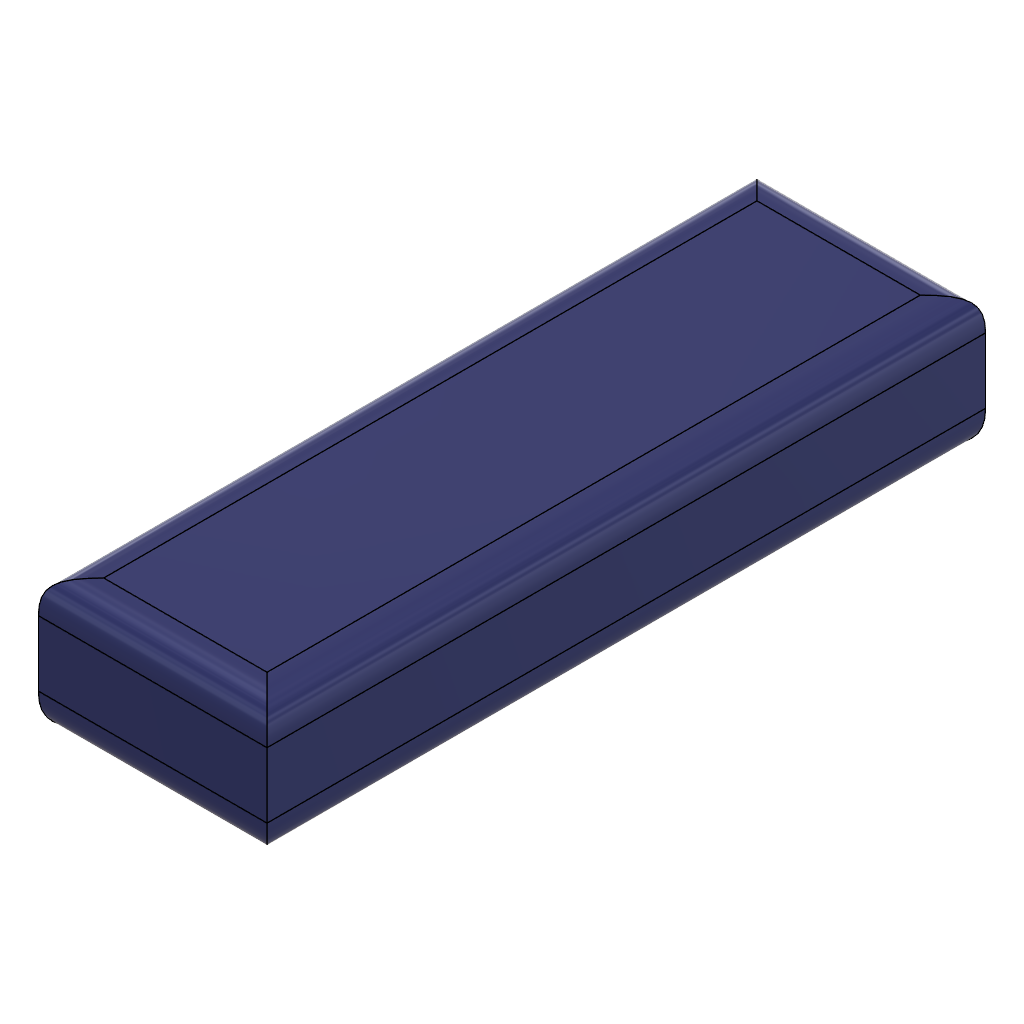
BALANCIN_V1 (Autodesk Fusion 360 archive; units mm, degrees)
design "BATERIA"
part number: 2026-09-12-01-15-48-725
Autodesk Fusion 360 part; units mm, degrees
sketch "Boceto1" plane through (0, 0, 0) normal (0, 1, 0) x (1, 0, 0)
  line L0 (163.423, 76.0371) -> (198.423, 76.0371)
  line L1 (198.423, 76.0371) -> (198.423, -33.9629)
  line L2 (198.423, -33.9629) -> (163.423, -33.9629)
  line L3 (163.423, -33.9629) -> (163.423, 76.0371)
  dimension "d1" = 35
  dimension "d2" = 110
  constraint horizontal L0
  constraint vertical L1
  constraint horizontal L2
  constraint vertical L3
  measures "d1" distance of L0.start L0.end
  measures "d2" distance of L0.start L2.end
extrude "Extruir1" add sketch "Boceto1" along normal blind 20
fillet "Empalme1" radius 5 tangency weight 2 4 edges at (198.423, 20, -21.0371) (180.923, 20, 33.9629) (163.423, 20, -21.0371) (180.923, 20, -76.0371)
fillet "Empalme2" radius 5 tangency weight 2 4 edges at (163.423, 0, -21.0371) (198.423, 0, -21.0371) (180.923, 0, 33.9629) (180.923, 0, -76.0371)

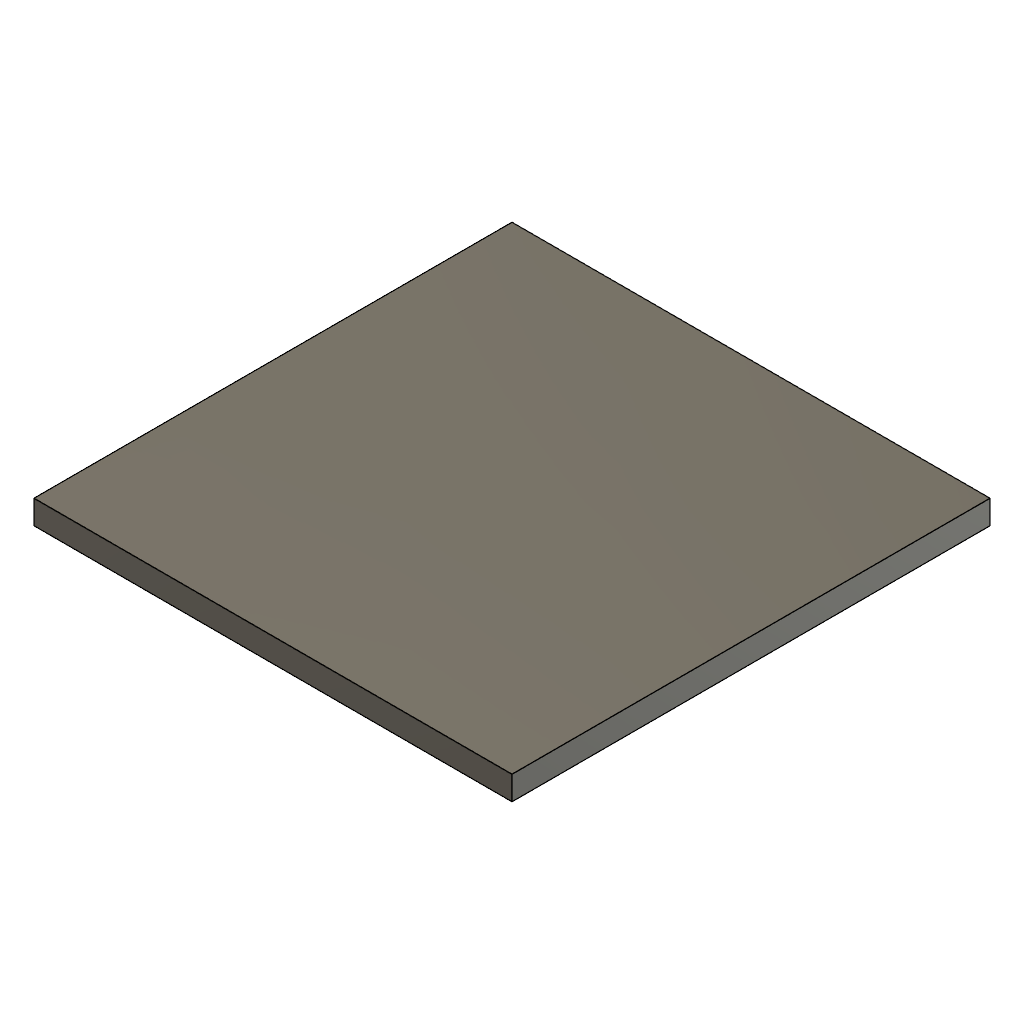
design "SUELO"
part number: 2026-09-16-12-44-53-559
Autodesk Fusion 360 part; units mm, degrees
sketch "Boceto1" plane through (0, 0, 0) normal (0, 1, 0) x (1, 0, 0)
  line L0 (100, 100) -> (-100, 100)
  line L1 (-100, 100) -> (-100, -100)
  line L2 (-100, -100) -> (100, -100)
  line L3 (100, -100) -> (100, 100)
  constraint horizontal L0
  constraint vertical L1
  constraint horizontal L2
  constraint vertical L3
extrude "Extruir1" add sketch "Boceto1" against normal blind 10
